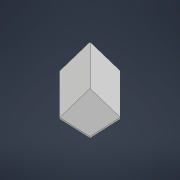
# Autodesk Inventor part: rubi
Saved by Autodesk Inventor 2022 (Build 260153000, 153)
## iProperties
Created: 2023-04-17
Part Number: rubi
Material: Generic
Document SubType Name: Modeling
Designer: cosminconstantin.ha
Density: 1 g/cm^3
Appearance: Default
Author: cosminconstantin.ha
Autodesk Inventor part; units mm, degrees
ref_plane "YZ Plane" through (0, 0, 0) normal (1, 0, 0) x (0, 1, 0)
ref_plane "XZ Plane" through (0, 0, 0) normal (0, 1, 0) x (-1, 0, 0)
ref_plane "XY Plane" through (0, 0, 0) normal (0, 0, 1) x (1, 0, 0)
sketch "Sketch1" plane through (0, 0, 0) normal (0, 0, 1) x (1, 0, 0)
  line L0 (-8, 13.2589) -> (8, 13.2589)
  line L1 (8, 13.2589) -> (8, -8.7411)
  line L2 (8, -8.7411) -> (-8, -8.7411)
  line L3 (-8, -8.7411) -> (-8, 13.2589)
  line L4 (-8, -0.0221) -> (0, 13.2589)
  line L5 (0, 13.2589) -> (8, 0.0221)
  line L6 (8, 0.0221) -> (0, -8.7411)
  line L7 (-8, -0.0221) -> (0, -8.7411)
  point P0 (0, 0)
  dimension "d0" = 16
  dimension "d1" = 22
  constraints: 16 end point, 2 midpoint, 2 parallel, 2 point on line, 1 horizontal, 1 perpendicular
  measures "d0" distance of L0.start L0.end
  measures "d1" distance between parallel lines of L0 L2
extrude "Extrusion1" add sketch "Sketch1" along normal blind 16 contours L5 L6 L7 L4
sketch "Sketch2" plane through (0, 0, 0) normal (1, 0, 0) x (0, 1, 0)
  line L0 (0.0221, 16) -> (13.2589, 16) projected
  line L1 (13.2589, 0) -> (13.2589, 16) projected
  line L2 (0.0221, 0) -> (13.2589, 0) projected
  line L3 (-8.7411, 0) -> (0.0221, 0) projected
  line L4 (-8.7411, 16) -> (0.0221, 16) projected
  line L5 (-8.7411, 0) -> (-8.7411, 16) projected
  line L6 (-0.0221, 0) -> (-0.0221, 16) projected
  line L7 (13.2589, 8) -> (-0.0221, 16)
  line L8 (-0.0221, 16) -> (-8.7411, 8)
  line L9 (-0.0221, 0) -> (-8.7411, 8)
  line L10 (-0.0221, 0) -> (13.2589, 8)
  point P0 (0, 0)
  constraints: 8 end point, 2 midpoint
extrude "Extrusion2" cut sketch "Sketch2" along normal mid plane 16 contours L0 L1 L7 L4 | L8 L5 L4 | L1 L2 L3 L10 | L3 L5 L9
sketch "Sketch4" plane through (0, 0, 0) normal (0, 1, 0) x (-1, 0, 0)
  line L0 (8, 0) -> (-7.9596, 0) projected
  line L1 (8, 0) -> (8, 16) projected
  line L2 (-7.9596, 16) -> (8, 16) projected
  line L3 (-8, 0.0266) -> (-8, 15.9734) projected
  line L4 (0, 0) -> (8, 8)
  line L5 (0.0202, 16) -> (8, 8)
  line L6 (0.0202, 16) -> (-8, 8)
  line L7 (-8, 8) -> (0, 0)
  constraints: 8 end point, 3 midpoint
extrude "Extrusion3" cut sketch "Sketch4" along normal mid plane 16 contours L0 L4 L1 | L5 L2 L1
mirror "Mirror1" about plane through (0, 0, 0) normal (1, 0, 0) of "Extrusion3"
body "Solid1"
